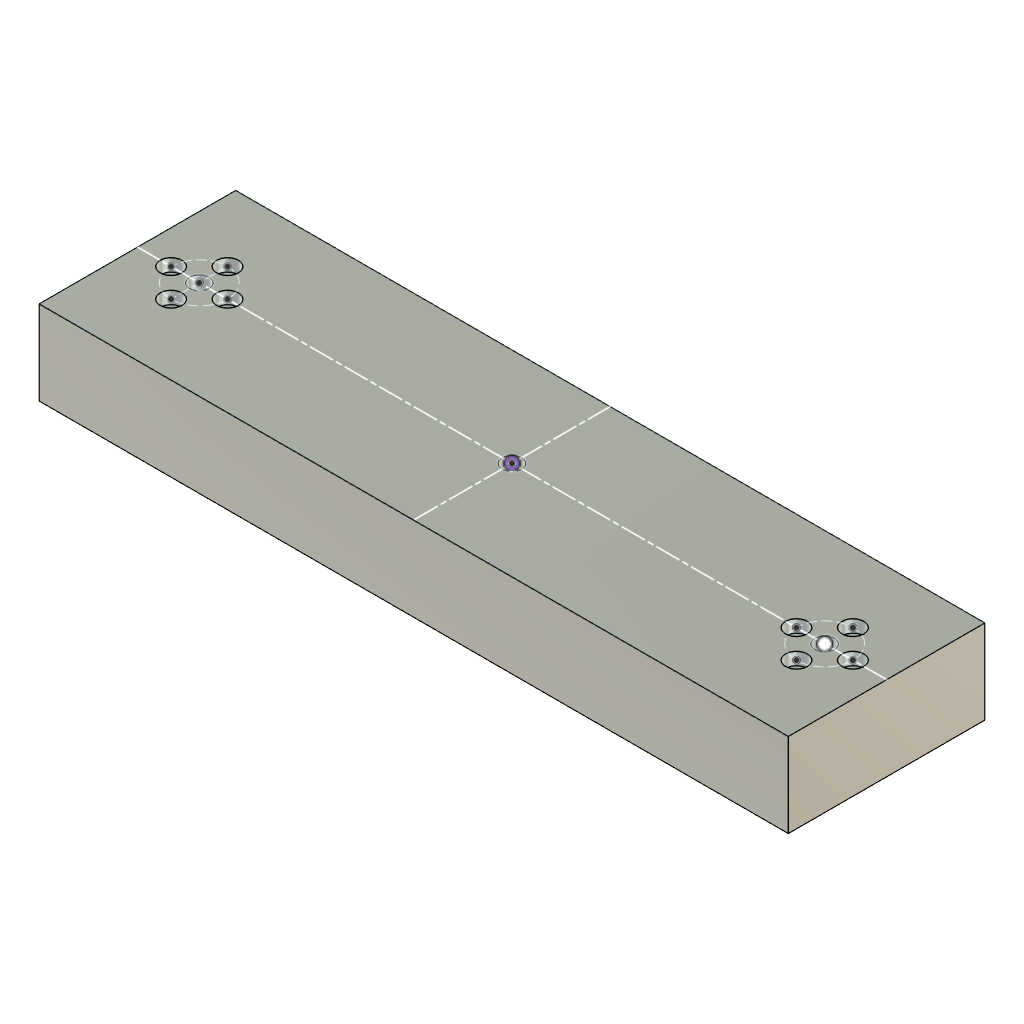
Tensile_Tester_Assembly (Autodesk Fusion 360 archive; units mm, degrees)
design "A10 Cross Head Plate"
part number: 2026-11-11-17-12-47-965
part number: 2026-11-11-17-17-20-266
Autodesk Fusion 360 part; units mm, degrees
sketch "Sketch1" plane through (0, 0, 0) normal (0, 0, 1) x (1, 0, 0)
  line L0 (190.5, 50) -> (-190.5, 50)
  line L1 (-190.5, 50) -> (-190.5, -50)
  line L2 (-190.5, -50) -> (190.5, -50)
  line L3 (190.5, -50) -> (190.5, 50)
  line L4 (190.5, 50) -> (-190.5, -50) construction
  line L5 (-190.5, 50) -> (190.5, -50) construction
  dimension "d1" = 381
  dimension "d2" = 100
  constraint horizontal L0
  constraint perpendicular L0 L1
  constraint parallel L0 L2
  constraint parallel L1 L3
  constraint coincident L4 origin
  constraint coincident L5 origin
  measures "d1" distance of L1.end L2.end
  measures "d2" distance of L0.end L1.end
extrude "Extrude1" add sketch "Sketch1" along normal blind 42.8 makes body 1
sketch "Sketch2" plane through (0, 0, 42.8) normal (0, 0, 1) x (-1, 0, 0)
  line L0 (-190.5, 50) -> (-190.5, -50)
  line L1 (-190.5, -50) -> (190.5, -50)
  line L2 (190.5, -50) -> (190.5, 50)
  line L3 (190.5, 50) -> (-190.5, 50)
  line L4 (190.5, 0) -> (-190.5, 0)
  line L5 (0, -50) -> (0, 50)
  circle A0 centre (159, 0) radius 14.351 construction
  circle A1 centre (159, 0) radius 5
  line L6 (159, -14.351) -> (159, 14.351) construction
  circle A2 centre (-159, 0) radius 14.351 construction
  circle A3 centre (-159, 0) radius 5
  circle A4 centre (0, 0) radius 5
  point P0 (144.649, 0)
  point P1 (173.351, 0)
  point P2 (159, -14.351)
  point P3 (159, 14.351)
  point P4 (-159, -14.351)
  point P5 (-144.649, 0)
  point P6 (-159, 14.351)
  point P7 (-173.351, 0)
  point P8 (-159, -14.351)
  point P9 (-173.351, 0)
  point P10 (-159, 14.351)
  point P11 (-144.649, 0)
  dimension "d5" = 28.702
  dimension "d6" = 10
  dimension "d7" = 31.5
  constraint midpoint L2 L4.start
  constraint midpoint L0 L4.end
  constraint midpoint L1 L5.start
  constraint midpoint L3 L5.end
  constraint coincident L4 A0.centre
  constraint concentric A0 A1
  constraint coincident A0 P0
  constraint coincident L4 P0
  constraint coincident A0 P1
  constraint coincident L4 P1
  constraint coincident A0 P2
  constraint coincident A0 P3
  constraint coincident P2 L6.start
  constraint coincident P3 L6.end
  constraint vertical L6
  constraint coincident A0.centre L6
  constraint symmetric L5 A0 A2
  constraint symmetric L5 A1 A3
  constraint symmetric L5 P0 P5
  constraint symmetric L5 P1 P9
  constraint symmetric L5 P2 P8
  constraint symmetric L5 P3 P10
  constraint coincident A4.centre origin
  constraint equal A1 A4
  constraint coincident P8 P4
  constraint coincident P9 P7
  constraint coincident P10 P6
  constraint coincident P11 P5
  measures "d5" diameter of A0
  measures "d6" diameter of A1
  measures "d7" distance of L2 A0.centre
hole "Hole1" at (-159, 14.351, 42.8) at (-144.649, 0, 42.8) at (-159, -14.351, 42.8) at (-173.351, 0, 42.8) at (144.649, 0, 42.8) at (159, 14.351, 42.8) at (173.351, 0, 42.8) at (159, -14.351, 42.8) direction (0, 0, -1) diameter 6.7564 depth 53.34 tip angle 118 counterbore diameter 11.1252 counterbore depth 6.35 bodies 1
extrude "Extrude2" cut sketch "Sketch2" against normal through all contours L4 A3 | L4 A3 | L4 L5 A4 | L4 L5 A4 | L4 L5 A4 | L4 L5 A4 | L4 A1 | L4 A1 bodies 1
copy_body "Body->Comp1" bodies 1 removing the originals makes body 2 in component "Cross Head Plate"
component "Cross Head Plate" placed x (1, 0, 0) y (0, 1, 0) z (0, 0, 1) at (0, 0, 0)
